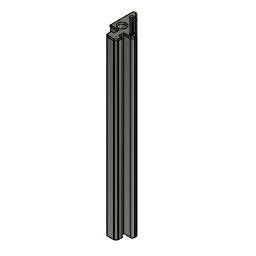
Neopixel_Holder (Autodesk Fusion 360 design; units mm, degrees)
Autodesk Fusion 360 part; units mm, degrees
sketch "Sketch1" plane through (0, 0, 0) normal (0, 0, 1) x (1, 0, 0)
  circle A0 centre (-47.221, -9.0323) radius 1.25
  line L0 (-40.721, -1.5323) -> (-53.721, -1.5323)
  line L1 (-54.721, -2.5323) -> (-54.721, -15.5323)
  line L2 (-53.721, -16.5323) -> (-40.721, -16.5323)
  line L3 (-39.721, -15.5323) -> (-39.721, -2.5323)
  line L4 (-39.721, -1.5323) -> (-54.721, -16.5323) construction
  line L5 (-54.721, -1.5323) -> (-39.721, -16.5323) construction
  line L6 (-47.221, -9.0323) -> (-47.221, -1.5323) construction
  line L7 (-48.921, -1.5323) -> (-48.921, -2.6323)
  line L8 (-48.921, -2.6323) -> (-50.071, -2.6323)
  line L9 (-50.071, -2.6323) -> (-50.071, -5.0823)
  line L10 (-50.071, -5.0823) -> (-48.921, -6.2323)
  line L11 (-48.921, -6.2323) -> (-47.221, -6.2323)
  line L12 (-45.521, -1.5323) -> (-45.521, -2.6323)
  line L13 (-45.521, -2.6323) -> (-44.371, -2.6323)
  line L14 (-44.371, -2.6323) -> (-44.371, -5.0823)
  line L15 (-44.371, -5.0823) -> (-45.521, -6.2323)
  line L16 (-45.521, -6.2323) -> (-47.221, -6.2323)
  line L17 (-54.721, -10.7323) -> (-53.621, -10.7323)
  line L18 (-53.621, -10.7323) -> (-53.621, -11.8823)
  line L19 (-53.621, -11.8823) -> (-51.171, -11.8823)
  line L20 (-51.171, -11.8823) -> (-50.021, -10.7323)
  line L21 (-50.021, -10.7323) -> (-50.021, -9.0323)
  line L22 (-50.021, -7.3323) -> (-50.021, -9.0323)
  line L23 (-51.171, -6.1823) -> (-50.021, -7.3323)
  line L24 (-53.621, -6.1823) -> (-51.171, -6.1823)
  line L25 (-53.621, -7.3323) -> (-53.621, -6.1823)
  line L26 (-54.721, -7.3323) -> (-53.621, -7.3323)
  line L27 (-45.521, -16.5323) -> (-45.521, -15.4323)
  line L28 (-45.521, -15.4323) -> (-44.371, -15.4323)
  line L29 (-44.371, -15.4323) -> (-44.371, -12.9823)
  line L30 (-44.371, -12.9823) -> (-45.521, -11.8323)
  line L31 (-45.521, -11.8323) -> (-47.221, -11.8323)
  line L32 (-48.921, -11.8323) -> (-47.221, -11.8323)
  line L33 (-50.071, -12.9823) -> (-48.921, -11.8323)
  line L34 (-50.071, -15.4323) -> (-50.071, -12.9823)
  line L35 (-48.921, -15.4323) -> (-50.071, -15.4323)
  line L36 (-48.921, -16.5323) -> (-48.921, -15.4323)
  line L37 (-39.721, -7.3323) -> (-40.821, -7.3323)
  line L38 (-40.821, -7.3323) -> (-40.821, -6.1823)
  line L39 (-40.821, -6.1823) -> (-43.271, -6.1823)
  line L40 (-43.271, -6.1823) -> (-44.421, -7.3323)
  line L41 (-44.421, -7.3323) -> (-44.421, -9.0323)
  line L42 (-44.421, -10.7323) -> (-44.421, -9.0323)
  line L43 (-43.271, -11.8823) -> (-44.421, -10.7323)
  line L44 (-40.821, -11.8823) -> (-43.271, -11.8823)
  line L45 (-40.821, -10.7323) -> (-40.821, -11.8823)
  line L46 (-39.721, -10.7323) -> (-40.821, -10.7323)
  arc A1 (-53.721, -1.5323) -> (-54.721, -2.5323) centre (-53.721, -2.5323) ccw
  arc A2 (-39.721, -2.5323) -> (-40.721, -1.5323) centre (-40.721, -2.5323) ccw
  arc A3 (-54.721, -15.5323) -> (-53.721, -16.5323) centre (-53.721, -15.5323) ccw
  arc A4 (-40.721, -16.5323) -> (-39.721, -15.5323) centre (-40.721, -15.5323) ccw
  point P0 (-47.221, -9.0323)
  point P1 (-47.221, -9.0323)
  dimension "d1" = 2.5
  dimension "d2" = 15
  dimension "d3" = 15
  dimension "d5" = 1.7
  dimension "d6" = 1.1
  dimension "d7" = 3.6
  dimension "d8" = 1.7
  dimension "d9" = 2.85
  dimension "d10" = 135
  dimension "d12" = 360
  dimension "d13" = 1
  dimension "d14" = 1
  dimension "d15" = 1
  dimension "d16" = 1
  constraint coincident P0 A0.centre
  constraint horizontal L0
  constraint perpendicular L0 L1
  constraint parallel L0 L2
  constraint parallel L1 L3
  constraint coincident L4 P1
  constraint coincident L5 P1
  constraint coincident L0 L7.start
  constraint perpendicular L0 L7
  constraint perpendicular L7 L8
  constraint perpendicular L0 L9
  constraint coincident L6 L11.end
  constraint perpendicular L6 L11
  constraint symmetric L6 L7.start L12.start
  constraint symmetric L6 L7.end L12.end
  constraint symmetric L6 L8.end L13.end
  constraint symmetric L6 L9.end L14.end
  constraint symmetric L6 L10.end L15.end
  constraint symmetric L6 L11.end L16.end
  constraint coincident L0 L6.end
  constraint coincident L5.start L0
  constraint coincident L5.start L1
  constraint tangent L0 A1
  constraint tangent L1 A1
  constraint coincident L4.start L0
  constraint coincident L4.start L3
  constraint tangent L0 A2
  constraint tangent L3 A2
  constraint coincident L4.end L1
  constraint coincident L4.end L2
  constraint tangent L1 A3
  constraint tangent L2 A3
  constraint coincident L5.end L3
  constraint coincident L5.end L2
  constraint tangent L3 A4
  constraint tangent L2 A4
  measures "d1" diameter of A0
  measures "d2" distance of L4.end L5.end
  measures "d3" distance of L5.start L4.end
  measures "d5" distance of L10.end L11.end
  measures "d6" distance of L7.start L7.end
  measures "d7" distance of L8 L11
  measures "d8" distance of L6.end L7.start
  measures "d9" distance of L6 L8.end
  measures "d10" angle of L10 L11
  measures "d13" radius of A1
  measures "d14" radius of A2
  measures "d15" radius of A3
  measures "d16" radius of A4
extrude "Extrude1" add sketch "Sketch1" along normal blind 15 contours L0 L1 L2 L3 L7 L8 L9 L10 L11 L12 L13 L14 L15 L16 L17 L18 L19 L20 L21 L22 L23 L24 L25 L26 L27 L28 L29 L30 L31 L32 L33 L34 L35 L36 L37 L38 L39 L40 L41 L42 L43 L44 L45 L46 A1 A2 A3 A4 makes body 1
sketch "Sketch2" plane through (0, 0, 15) normal (0, 0, 1) x (-1, 0, 0)
  circle A0 centre (47.221, 9.0323) radius 1.25
  line L0 (45.521, 16.5323) -> (40.721, 16.5323)
  arc A1 (40.721, 16.5323) -> (39.721, 15.5323) centre (40.721, 15.5323) ccw
  line L1 (39.721, 15.5323) -> (39.721, 10.7323)
  line L2 (39.721, 10.7323) -> (40.821, 10.7323)
  line L3 (40.821, 10.7323) -> (40.821, 11.8823)
  line L4 (40.821, 11.8823) -> (43.271, 11.8823)
  line L5 (43.271, 11.8823) -> (44.421, 10.7323)
  line L6 (44.421, 10.7323) -> (44.421, 7.3323)
  line L7 (44.421, 7.3323) -> (43.271, 6.1823)
  line L8 (43.271, 6.1823) -> (40.821, 6.1823)
  line L9 (40.821, 6.1823) -> (40.821, 7.3323)
  line L10 (40.821, 7.3323) -> (39.721, 7.3323)
  line L11 (39.721, 7.3323) -> (39.721, 2.5323)
  arc A2 (39.721, 2.5323) -> (40.721, 1.5323) centre (40.721, 2.5323) ccw
  line L12 (40.721, 1.5323) -> (45.521, 1.5323)
  line L13 (45.521, 1.5323) -> (45.521, 2.6323)
  line L14 (45.521, 2.6323) -> (44.371, 2.6323)
  line L15 (44.371, 2.6323) -> (44.371, 5.0823)
  line L16 (44.371, 5.0823) -> (45.521, 6.2323)
  line L17 (45.521, 6.2323) -> (48.921, 6.2323)
  line L18 (48.921, 6.2323) -> (50.071, 5.0823)
  line L19 (50.071, 5.0823) -> (50.071, 2.6323)
  line L20 (50.071, 2.6323) -> (48.921, 2.6323)
  line L21 (48.921, 2.6323) -> (48.921, 1.5323)
  line L22 (48.921, 1.5323) -> (53.721, 1.5323)
  arc A3 (53.721, 1.5323) -> (54.721, 2.5323) centre (53.721, 2.5323) ccw
  line L23 (54.721, 2.5323) -> (54.721, 7.3323)
  line L24 (54.721, 7.3323) -> (53.621, 7.3323)
  line L25 (53.621, 7.3323) -> (53.621, 6.1823)
  line L26 (53.621, 6.1823) -> (51.171, 6.1823)
  line L27 (51.171, 6.1823) -> (50.021, 7.3323)
  line L28 (50.021, 7.3323) -> (50.021, 10.7323)
  line L29 (50.021, 10.7323) -> (51.171, 11.8823)
  line L30 (51.171, 11.8823) -> (53.621, 11.8823)
  line L31 (53.621, 11.8823) -> (53.621, 10.7323)
  line L32 (53.621, 10.7323) -> (54.721, 10.7323)
  line L33 (54.721, 10.7323) -> (54.721, 15.5323)
  arc A4 (54.721, 15.5323) -> (53.721, 16.5323) centre (53.721, 15.5323) ccw
  line L34 (53.721, 16.5323) -> (48.921, 16.5323)
  line L35 (48.921, 16.5323) -> (48.921, 15.4323)
  line L36 (48.921, 15.4323) -> (50.071, 15.4323)
  line L37 (50.071, 15.4323) -> (50.071, 12.9823)
  line L38 (50.071, 12.9823) -> (48.921, 11.8323)
  line L39 (48.921, 11.8323) -> (45.521, 11.8323)
  line L40 (45.521, 11.8323) -> (44.371, 12.9823)
  line L41 (44.371, 12.9823) -> (44.371, 15.4323)
  line L42 (44.371, 15.4323) -> (45.521, 15.4323)
  line L43 (45.521, 15.4323) -> (45.521, 16.5323)
  arc A5 (53.721, 1.3323) -> (54.921, 2.5323) centre (53.721, 2.5323) ccw
  line L44 (54.921, 2.5323) -> (54.921, 7.5323)
  line L45 (54.921, 7.5323) -> (53.421, 7.5323)
  line L46 (53.421, 7.5323) -> (53.421, 6.3823)
  line L47 (53.421, 6.3823) -> (51.2539, 6.3823)
  line L48 (51.2539, 6.3823) -> (50.221, 7.4151)
  line L49 (50.221, 7.4151) -> (50.221, 10.6494)
  line L50 (50.221, 10.6494) -> (51.2539, 11.6823)
  line L51 (51.2539, 11.6823) -> (53.421, 11.6823)
  line L52 (53.421, 11.6823) -> (53.421, 10.5323)
  line L53 (53.421, 10.5323) -> (54.921, 10.5323)
  line L54 (54.921, 10.5323) -> (54.921, 15.5323)
  arc A6 (54.921, 15.5323) -> (53.721, 16.7323) centre (53.721, 15.5323) ccw
  line L55 (53.721, 16.7323) -> (48.721, 16.7323)
  line L56 (48.721, 16.7323) -> (48.721, 15.2323)
  line L57 (48.721, 15.2323) -> (49.871, 15.2323)
  line L58 (49.871, 15.2323) -> (49.871, 13.0651)
  line L59 (49.871, 13.0651) -> (48.8382, 12.0323)
  line L60 (48.8382, 12.0323) -> (45.6039, 12.0323)
  line L61 (45.6039, 12.0323) -> (44.571, 13.0651)
  line L62 (44.571, 13.0651) -> (44.571, 15.2323)
  line L63 (44.571, 15.2323) -> (45.721, 15.2323)
  line L64 (45.721, 15.2323) -> (45.721, 16.7323)
  line L65 (45.721, 16.7323) -> (40.721, 16.7323)
  arc A7 (40.721, 16.7323) -> (39.521, 15.5323) centre (40.721, 15.5323) ccw
  line L66 (39.521, 15.5323) -> (39.521, 10.5323)
  line L67 (39.521, 10.5323) -> (41.021, 10.5323)
  line L68 (41.021, 10.5323) -> (41.021, 11.6823)
  line L69 (41.021, 11.6823) -> (43.1882, 11.6823)
  line L70 (43.1882, 11.6823) -> (44.221, 10.6494)
  line L71 (44.221, 10.6494) -> (44.221, 7.4151)
  line L72 (44.221, 7.4151) -> (43.1882, 6.3823)
  line L73 (43.1882, 6.3823) -> (41.021, 6.3823)
  line L74 (41.021, 6.3823) -> (41.021, 7.5323)
  line L75 (41.021, 7.5323) -> (39.521, 7.5323)
  line L76 (39.521, 7.5323) -> (39.521, 2.5323)
  arc A8 (39.521, 2.5323) -> (40.721, 1.3323) centre (40.721, 2.5323) ccw
  line L77 (40.721, 1.3323) -> (45.721, 1.3323)
  line L78 (45.721, 1.3323) -> (45.721, 2.8323)
  line L79 (45.721, 2.8323) -> (44.571, 2.8323)
  line L80 (44.571, 2.8323) -> (44.571, 4.9994)
  line L81 (44.571, 4.9994) -> (45.6039, 6.0323)
  line L82 (45.6039, 6.0323) -> (48.8382, 6.0323)
  line L83 (48.8382, 6.0323) -> (49.871, 4.9994)
  line L84 (49.871, 4.9994) -> (49.871, 2.8323)
  line L85 (49.871, 2.8323) -> (48.721, 2.8323)
  line L86 (48.721, 2.8323) -> (48.721, 1.3323)
  line L87 (48.721, 1.3323) -> (53.721, 1.3323)
  line L88 (48.721, 1.3323) -> (45.721, 1.3323) construction
  line L89 (47.221, 1.3323) -> (47.221, 9.0323) construction
  line L90 (52.721, 1.3323) -> (52.721, -11.6677)
  line L91 (41.721, 1.3323) -> (41.721, -0.6677)
  line L92 (52.721, -11.6677) -> (41.721, -0.6677)
  line L93 (43.438, -2.3847) -> (44.4279, -1.3947)
  line L94 (44.4279, -1.3947) -> (43.5794, -0.5462)
  line L95 (43.5794, -0.5462) -> (43.8623, -0.2634)
  line L96 (43.8623, -0.2634) -> (50.5798, -6.9809)
  line L97 (50.5798, -6.9809) -> (50.2969, -7.2637)
  line L98 (50.2969, -7.2637) -> (49.4484, -6.4152)
  line L99 (49.4484, -6.4152) -> (48.4584, -7.4052)
  line L100 (47.221, 1.3323) -> (47.221, -3.6221) construction
  circle A9 centre (50.4383, -7.1223) radius 0.4
  circle A10 centre (43.7208, -0.4048) radius 0.4
  dimension "d19" = 0.2
  dimension "d29" = 45
  dimension "d32" = 1.4
  dimension "d34" = 0.4
  dimension "d35" = 9.5
  dimension "d37" = 1.2
  dimension "d39" = 1.2
  dimension "d42" = 2
  dimension "d43" = 4
  dimension "d45" = 4
  dimension "d56" = 0.4
  dimension "d57" = 0.8
  dimension "d58" = 0.8
  constraint midpoint L88 L89.start
  constraint coincident A0.centre L89.end
  constraint coincident L87 L90.start
  constraint perpendicular L87 L90
  constraint coincident L77 L91.start
  constraint perpendicular L77 L91
  constraint coincident L92 L93.start
  constraint perpendicular L92 L93
  constraint perpendicular L93 L94
  constraint perpendicular L94 L95
  constraint perpendicular L93 L96
  constraint perpendicular L94 L97
  constraint perpendicular L97 L98
  constraint coincident L92 L99.end
  constraint perpendicular L92 L99
  constraint perpendicular L88 L100
  constraint midpoint L96 L100.end
  constraint midpoint L97 A9.centre
  constraint midpoint L95 A10.centre
  measures "d29" angle of L77 L92
  measures "d32" distance of L92 L98
  measures "d34" distance of L94.end L95.end
  measures "d35" distance of L95.end L96.end
  measures "d37" distance of L93.end L94.end
  measures "d39" distance of L97.end L98.end
  measures "d42" distance of L91.start L91.end
  measures "d43" distance of L86.end L90
  measures "d45" distance of L77.end L91.start
  measures "d56" distance of L96.end L97.end
  measures "d57" diameter of A9
  measures "d58" diameter of A10
extrude "Extrude2" add sketch "Sketch2" along normal blind 80 separate body contours L77 L78 L79 L80 L81 L82 L83 L84 L85 L86 L87 L90 L91 L92 L93 L94 L96 L98 L99 A9 A10 makes body 2
fillet "Fillet2" radius 0.4 6 edges at (-44.571, -4.9994, 55) (-45.6039, -6.0323, 55) (-44.571, -2.8323, 55) (-49.871, -2.8323, 55) (-49.871, -4.9994, 55) (-48.8382, -6.0323, 55) on bodies 2
fillet "Fillet2" radius 1 2 edges at (-41.721, -1.3323, 55) (-52.721, -1.3323, 55) on bodies 2
fillet "Fillet2" radius 1 1 edges at (-41.721, 0.6677, 55) on bodies 2
fillet "Fillet2" radius 0.4 4 edges at (-49.4484, 6.4152, 55) (-48.4584, 7.4052, 55) (-44.4279, 1.3947, 55) (-43.438, 2.3847, 55) on bodies 2
fillet "Fillet2" radius 1 1 edges at (-52.721, 11.6677, 55) on bodies 2
fillet "Fillet3" radius 0.4 4 edges at (-50.052, 7.0188, 55) (-50.3348, 6.7359, 55) (-43.8244, 0.7912, 55) (-44.1072, 0.5083, 55) on bodies 2
sketch "Sketch3" plane through (0, 0, 95) normal (0, 0, 1) x (-1, 0, 0)
  arc A0 (44.12, -0.3798) -> (44.2364, -0.6375) centre (44.5193, -0.3547) ccw
  line L0 (44.2364, -0.6375) -> (50.2056, -6.6067)
  arc A1 (50.2056, -6.6067) -> (50.4634, -6.7231) centre (50.4884, -6.3239) ccw
  arc A2 (50.0391, -7.1474) -> (50.4634, -6.7231) centre (50.4383, -7.1223) ccw
  arc A3 (50.0391, -7.1474) -> (49.9228, -6.8896) centre (49.6399, -7.1724) ccw
  line L1 (49.9228, -6.8896) -> (49.7312, -6.6981)
  arc A4 (49.7312, -6.6981) -> (49.1656, -6.6981) centre (49.4484, -6.9809) ccw
  line L2 (49.1656, -6.6981) -> (48.7413, -7.1223)
  arc A5 (48.7413, -7.1223) -> (48.7413, -7.688) centre (49.0241, -7.4052) ccw
  line L3 (48.7413, -7.688) -> (51.0139, -9.9606)
  arc A6 (51.0139, -9.9606) -> (52.721, -9.2535) centre (51.721, -9.2535) ccw
  line L4 (52.721, -9.2535) -> (52.721, 0.3323)
  arc A7 (52.721, 0.3323) -> (51.721, 1.3323) centre (51.721, 0.3323) ccw
  line L5 (51.721, 1.3323) -> (48.721, 1.3323)
  line L6 (48.721, 1.3323) -> (48.721, 2.8323)
  line L7 (48.721, 2.8323) -> (49.471, 2.8323)
  arc A8 (49.471, 2.8323) -> (49.871, 3.2323) centre (49.471, 3.2323) ccw
  line L8 (49.871, 3.2323) -> (49.871, 4.8338)
  arc A9 (49.871, 4.8338) -> (49.7539, 5.1166) centre (49.471, 4.8338) ccw
  line L9 (49.7539, 5.1166) -> (48.9553, 5.9151)
  arc A10 (48.9553, 5.9151) -> (48.6725, 6.0323) centre (48.6725, 5.6323) ccw
  line L10 (48.6725, 6.0323) -> (45.7695, 6.0323)
  arc A11 (45.7695, 6.0323) -> (45.4867, 5.9151) centre (45.7695, 5.6323) ccw
  line L11 (45.4867, 5.9151) -> (44.6882, 5.1166)
  arc A12 (44.6882, 5.1166) -> (44.571, 4.8338) centre (44.971, 4.8338) ccw
  line L12 (44.571, 4.8338) -> (44.571, 3.2323)
  arc A13 (44.571, 3.2323) -> (44.971, 2.8323) centre (44.971, 3.2323) ccw
  line L13 (44.971, 2.8323) -> (45.721, 2.8323)
  line L14 (45.721, 2.8323) -> (45.721, 1.3323)
  line L15 (45.721, 1.3323) -> (42.721, 1.3323)
  arc A14 (42.721, 1.3323) -> (41.721, 0.3323) centre (42.721, 0.3323) ccw
  line L16 (41.721, 0.3323) -> (41.721, -0.2535)
  arc A15 (41.721, -0.2535) -> (42.0139, -0.9606) centre (42.721, -0.2535) ccw
  line L17 (42.0139, -0.9606) -> (43.1551, -2.1019)
  arc A16 (43.1551, -2.1019) -> (43.7208, -2.1019) centre (43.438, -1.819) ccw
  line L18 (43.7208, -2.1019) -> (44.1451, -1.6776)
  arc A17 (44.1451, -1.6776) -> (44.1451, -1.1119) centre (43.8623, -1.3947) ccw
  line L19 (44.1451, -1.1119) -> (43.9536, -0.9204)
  arc A18 (43.9536, -0.9204) -> (43.6958, -0.804) centre (43.6707, -1.2032) ccw
  arc A19 (44.12, -0.3798) -> (43.6958, -0.804) centre (43.7208, -0.4048) ccw
  line L20 (47.221, -3.6221) -> (49.3423, -1.5008) construction
  circle A20 centre (49.3423, -1.5008) radius 1.5
  dimension "d61" = 3
  dimension "d63" = 3
  constraint midpoint L0 L20.start
  constraint perpendicular L0 L20
  constraint coincident L20.end A20.centre
  measures "d61" diameter of A20
  measures "d63" distance of L20.start L20.end
extrude "Extrude3" cut sketch "Sketch3" against normal up to surface (80 mm away) contours A20 bodies 2
chamfer "Chamfer1" distance 0.4 angle 45 2 faces at (-52.0789, 5.2872, 95) (-52.0789, 5.2872, 15) on bodies 2
hidden bodies 1
equation "d5 = ( 3.4 / 2 ) * 1 mm"
equation "d9 = ( 5.7 / 2 ) * 1 mm"
named bodies: "Extrusion", "NeopixelHolder"
